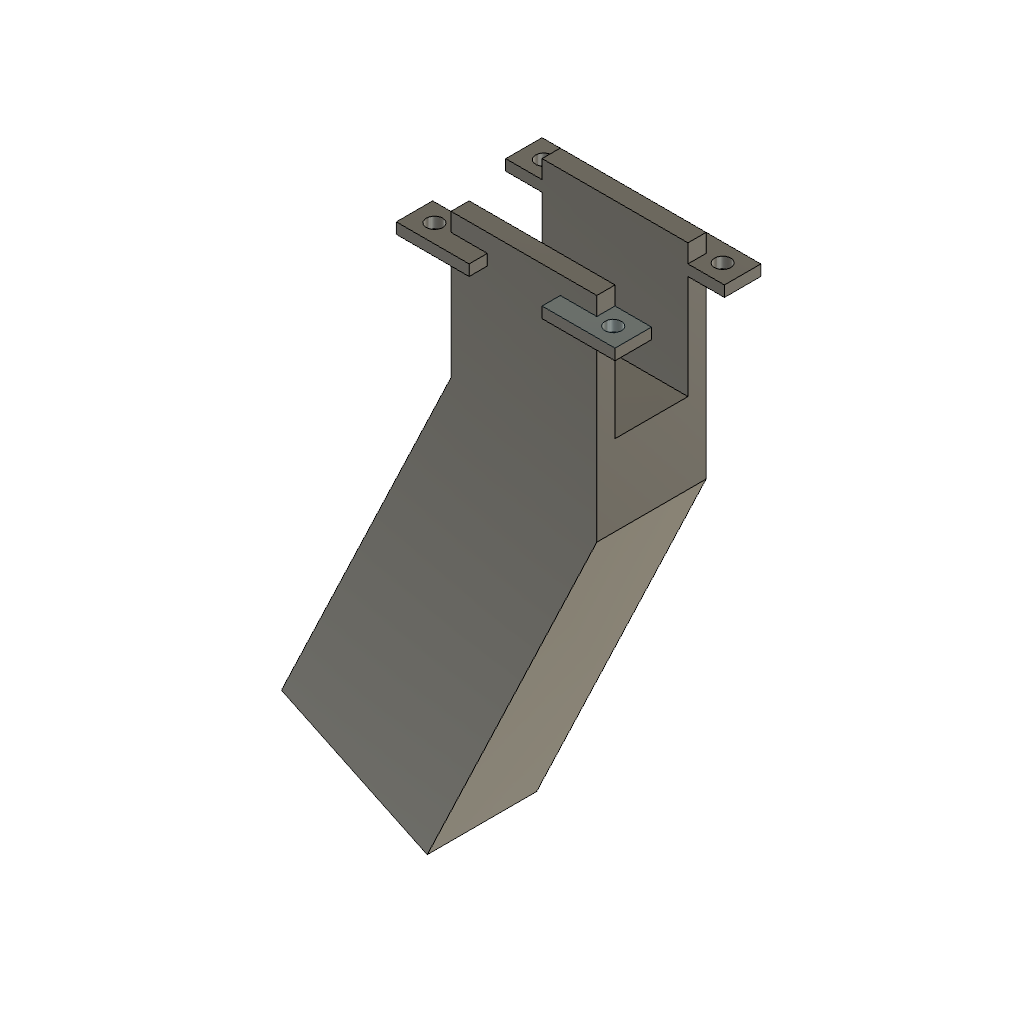
Servo Cover (Autodesk Fusion 360 design; units mm, degrees)
Autodesk Fusion 360 part; units mm, degrees
sketch "Sketch1" plane through (0, 0, 0) normal (0, 0, 1) x (1, 0, 0)
  line L0 (25, 15) -> (-25, 15)
  line L1 (-25, 15) -> (-25, -15)
  line L2 (-25, -15) -> (25, -15)
  line L3 (25, -15) -> (25, 15)
  line L4 (25, 15) -> (-25, -15) construction
  line L5 (-25, 15) -> (25, -15) construction
  line L6 (20, 10) -> (-20, 10)
  line L7 (-20, 10) -> (-20, -10)
  line L8 (-20, -10) -> (20, -10)
  line L9 (20, -10) -> (20, 10)
  line L10 (20, 10) -> (-20, -10) construction
  line L11 (-20, 10) -> (20, -10) construction
  line L12 (-20, -10) -> (-25, -10)
  line L13 (-20, 10) -> (-25, 10)
  line L14 (20, -10) -> (25, -10)
  line L15 (20, 10) -> (25, 10)
  line L16 (20, 7) -> (25, 7)
  line L17 (20, -7) -> (25, -7)
  line L18 (20, 10) -> (20, 15)
  line L19 (20, -10) -> (20, -15)
  line L20 (-20, 10) -> (-20, 15)
  line L21 (-20, -10) -> (-20, -15)
  dimension "d1" = 50
  dimension "d2" = 30
  dimension "d3" = 40
  dimension "d4" = 20
  dimension "d5" = 3
  dimension "d6" = 3
  constraint horizontal L0
  constraint perpendicular L0 L1
  constraint parallel L0 L2
  constraint parallel L1 L3
  constraint coincident L4 origin
  constraint coincident L5 origin
  constraint horizontal L6
  constraint perpendicular L6 L7
  constraint parallel L6 L8
  constraint parallel L7 L9
  constraint coincident L10 origin
  constraint coincident L11 origin
  constraint coincident L1 L12.end
  constraint perpendicular L1 L12
  constraint coincident L1 L13.end
  constraint perpendicular L1 L13
  constraint coincident L3 L14.end
  constraint perpendicular L3 L14
  constraint coincident L3 L15.end
  constraint perpendicular L3 L15
  constraint coincident L9 L16.start
  constraint coincident L3 L16.end
  constraint perpendicular L3 L16
  constraint coincident L9 L17.start
  constraint coincident L3 L17.end
  constraint perpendicular L3 L17
  constraint coincident L0 L18.end
  constraint perpendicular L0 L18
  constraint coincident L2 L19.end
  constraint perpendicular L2 L19
  constraint coincident L0 L20.end
  constraint perpendicular L0 L20
  constraint coincident L2 L21.end
  constraint perpendicular L2 L21
  measures "d1" distance of L1.end L2.end
  measures "d2" distance of L0.end L1.end
  measures "d3" distance of L7.end L8.end
  measures "d4" distance of L6.end L7.end
  measures "d5" distance of L14 L17
  measures "d6" distance of L15 L16
extrude "Extrude1" add sketch "Sketch1" along normal blind 36.5 contours L0 L6 L18 L20 | L2 L8 L19 L21 makes body 1 at (6.6667, 10, 12.1667) makes body 2 at (-6.6667, -10, 12.1667)
extrude "Extrude4" add sketch "Sketch1" against normal blind 3 contours L0 L6 L18 L20 | L6 L7 L8 L9 | L2 L8 L19 L21 bodies 1 2
sketch "Sketch17" plane through (20, 0, 0) normal (1, 0, 0) x (0, 1, 0)
  line L0 (15, -3) -> (15, 36.5)
  line L1 (15, 36.5) -> (10, 36.5)
  line L2 (10, 36.5) -> (10, 0)
  line L3 (10, 0) -> (-10, 0)
  line L4 (-10, 0) -> (-10, 36.5)
  line L5 (-10, 36.5) -> (-15, 36.5)
  line L6 (-15, 36.5) -> (-15, -3)
  line L7 (-15, -3) -> (15, -3)
  line L8 (-15, 31.5) -> (15, 31.5)
  line L9 (15, 31.5) -> (15, 28.5)
  line L10 (15, 28.5) -> (-15, 28.5)
  line L11 (-15, 28.5) -> (-15, 31.5)
  line L12 (-10, 31.5) -> (-10, 28.5)
  line L13 (10, 31.5) -> (10, 28.5)
  dimension "d34" = 3
  dimension "d35" = 31.5
  constraint horizontal L8
  constraint vertical L9
  constraint horizontal L10
  constraint vertical L11
  constraint coincident L6 L8.start
  constraint coincident L4 L12.start
  constraint coincident L8 L12.start
  constraint coincident L10 L12.end
  constraint coincident L4 L12.end
  constraint coincident L2 L13.start
  constraint coincident L8 L13.start
  constraint coincident L10 L13.end
  constraint coincident L2 L13.end
  measures "d34" distance of L8.start L10.end
  measures "d35" distance of L3 L8
extrude "Extrude9" add sketch "Sketch17" along normal blind 10 contours L0 L2 L8 L9 L10 L13 | L4 L6 L8 L10 L11 L12 bodies 1
sketch "Sketch18" plane through (0, -15, 0) normal (0, -1, 0) x (1, 0, 0)
  line L0 (20, -3) -> (20, 28.5)
  line L1 (20, 28.5) -> (30, 28.5)
  line L2 (30, 28.5) -> (30, 31.5)
  line L3 (30, 31.5) -> (20, 31.5)
  line L4 (20, 31.5) -> (20, 36.5)
  line L5 (20, 36.5) -> (-20, 36.5)
  line L6 (-20, -3) -> (20, -3)
  line L7 (30, 31.5) -> (10, 31.5)
  line L8 (20, 28.5) -> (10, 28.5)
  line L9 (10, 28.5) -> (10, 31.5)
  line L10 (10, 31.5) -> (30, 31.5)
  line L11 (30, 31.5) -> (30, 28.5)
  line L12 (30, 28.5) -> (10, 28.5)
  line L13 (10, 28.5) -> (10, 31.5)
  line L14 (-20, 36.5) -> (-20, -3)
  dimension "d49" = 20
  constraint horizontal L7
  constraint coincident L2.end L3.start
  constraint coincident L0.end L1.start
  constraint perpendicular L7 L9
  constraint horizontal L10
  constraint vertical L11
  constraint horizontal L12
  constraint vertical L13
  constraint coincident L1.end L2.start
  measures "d49" distance of L2.end L7.end
sketch "Sketch19" plane through (0, 15, 0) normal (0, 1, 0) x (-1, 0, 0)
  line L0 (20, 36.5) -> (-20, 36.5)
  line L1 (-20, 36.5) -> (-20, 31.5)
  line L2 (-20, 31.5) -> (-30, 31.5)
  line L3 (-30, 31.5) -> (-30, 28.5)
  line L4 (-30, 28.5) -> (-20, 28.5)
  line L5 (-20, 28.5) -> (-20, -3)
  line L6 (-20, -3) -> (20, -3)
  line L7 (-30, 31.5) -> (-10, 31.5)
  line L8 (-10, 31.5) -> (-10, 28.5)
  line L9 (-10, 28.5) -> (-30, 28.5)
  line L10 (-30, 28.5) -> (-30, 31.5)
  line L11 (20, -3) -> (20, 36.5)
  dimension "d50" = 20
  dimension "d51" = 3
  constraint horizontal L7
  constraint vertical L8
  constraint horizontal L9
  constraint vertical L10
  constraint coincident L2.end L3.start
  measures "d50" distance of L2.end L7.end
  measures "d51" distance of L2.end L3.end
extrude "Extrude10" add sketch "Sketch19" along normal blind 5 contours L2 L3 L4 L7 L8 L9 L10 bodies 1
extrude "Extrude11" add sketch "Sketch18" along normal blind 5 contours L1 L2 L3 L7 L8 L9 L10 L11 L12 L13 bodies 1
sketch "Sketch20" plane through (0, 0, 31.5) normal (0, 0, 1) x (-1, 0, 0)
  line L0 (-20, 10) -> (-20, 15)
  line L1 (-10, 20) -> (-30, 20)
  line L2 (-30, 20) -> (-30, 10)
  line L3 (-30, 10) -> (-20, 10)
  line L4 (-10, -20) -> (-30, -20)
  line L5 (-30, -20) -> (-30, -10)
  circle A0 centre (-24.5, -15) radius 2.25
  line L6 (-20, -10) -> (-20, -15)
  circle A1 centre (-24.5, 15) radius 2.25
  line L7 (-20, 15) -> (-10, 15)
  line L8 (-10, 15) -> (-10, 20)
  point P0 (-20, -10)
  point P1 (-30, -20)
  point P2 (-30, -10)
  dimension "d43" = 4.5
  dimension "d44" = 4.5
  dimension "d45" = 4.5
  dimension "d46" = 4.5
  constraint coincident P1 L4.end
  constraint coincident P2 L5.end
  measures "d43" diameter of A0
  measures "d44" distance of A0.centre L6
  measures "d45" diameter of A1
  measures "d46" distance of L0 A1.centre
extrude "Extrude12" cut sketch "Sketch20" against normal blind 3 contours A0 | A1 bodies 1
sketch "Sketch24" plane through (-20, 0, 0) normal (-1, 0, 0) x (0, -1, 0)
  line L0 (-10, 0) -> (-10, 36.5)
  line L1 (-10, 36.5) -> (-15, 36.5)
  line L2 (-15, 36.5) -> (-15, -3)
  line L3 (-15, -3) -> (15, -3)
  line L4 (15, -3) -> (15, 36.5)
  line L5 (15, 36.5) -> (10, 36.5)
  line L6 (10, 36.5) -> (10, 0)
  line L7 (10, 0) -> (-10, 0)
  line L8 (-20, 31.5) -> (20, 31.5)
  line L9 (20, 31.5) -> (20, 28.5)
  line L10 (20, 28.5) -> (-20, 28.5)
  line L11 (-20, 28.5) -> (-20, 31.5)
  line L12 (-10, 31.5) -> (-10, 28.5)
  line L13 (10, 31.5) -> (10, 28.5)
  line L14 (15, 31.5) -> (15, 28.5)
  line L15 (-15, 31.5) -> (-15, 28.5)
  point P0 (-20, 31.5)
  point P1 (20, 28.5)
  constraint horizontal L8
  constraint vertical L9
  constraint horizontal L10
  constraint vertical L11
  constraint coincident P1 L9.end
  constraint coincident P0 L8.start
  constraint coincident L8 L12.start
  constraint coincident L0 L12.start
  constraint coincident L10 L12.end
  constraint coincident L0 L12.end
  constraint coincident L6 L13.start
  constraint coincident L8 L13.start
  constraint coincident L10 L13.end
  constraint coincident L6 L13.end
  constraint coincident L4 L14.start
  constraint coincident L8 L14.start
  constraint coincident L4 L14.end
  constraint coincident L10 L14.end
  constraint coincident L8 L15.start
  constraint coincident L2 L15.start
  constraint coincident L10 L15.end
  constraint coincident L2 L15.end
extrude "Extrude13" add sketch "Sketch24" along normal blind 10 contours L0 L2 L8 L10 L12 L15 | L4 L6 L8 L10 L13 L14 bodies 1
sketch "Sketch25" plane through (0, 15, 0) normal (0, 1, 0) x (-1, 0, 0)
  line L0 (-10, 28.5) -> (-20, 28.5)
  line L1 (-20, 28.5) -> (-20, -3)
  line L2 (-20, -3) -> (20, -3)
  line L3 (20, -3) -> (20, 28.5)
  line L4 (20, 28.5) -> (30, 28.5)
  line L5 (30, 28.5) -> (30, 31.5)
  line L6 (30, 31.5) -> (20, 31.5)
  line L7 (20, 31.5) -> (20, 36.5)
  line L8 (20, 36.5) -> (-20, 36.5)
  line L9 (-20, 36.5) -> (-20, 31.5)
  line L10 (-20, 31.5) -> (-10, 31.5)
  line L11 (-10, 31.5) -> (-10, 28.5)
  line L12 (30, 31.5) -> (10, 31.5)
  line L13 (10, 31.5) -> (10, 28.5)
  line L14 (10, 28.5) -> (30, 28.5)
  line L15 (30, 28.5) -> (30, 31.5)
  dimension "d54" = 20
  constraint horizontal L12
  constraint vertical L13
  constraint horizontal L14
  constraint vertical L15
  constraint coincident L5.end L6.start
  measures "d54" distance of L5.end L12.end
extrude "Extrude14" add sketch "Sketch25" along normal blind 5 contours L4 L5 L6 L12 L13 L14 L15 bodies 1
sketch "Sketch26" plane through (0, -15, 0) normal (0, -1, 0) x (1, 0, 0)
  line L0 (10, 31.5) -> (20, 31.5)
  line L1 (20, 31.5) -> (20, 36.5)
  line L2 (20, 36.5) -> (-20, 36.5)
  line L3 (-20, 36.5) -> (-20, 31.5)
  line L4 (-20, 31.5) -> (-30, 31.5)
  line L5 (-30, 31.5) -> (-30, 28.5)
  line L6 (-30, 28.5) -> (-20, 28.5)
  line L7 (-20, 28.5) -> (-20, -3)
  line L8 (-20, -3) -> (20, -3)
  line L9 (20, -3) -> (20, 28.5)
  line L10 (20, 28.5) -> (10, 28.5)
  line L11 (10, 28.5) -> (10, 31.5)
  line L12 (-30, 31.5) -> (-10, 31.5)
  line L13 (-10, 31.5) -> (-10, 28.5)
  line L14 (-10, 28.5) -> (-30, 28.5)
  line L15 (-30, 28.5) -> (-30, 31.5)
  dimension "d57" = 20
  constraint horizontal L12
  constraint vertical L13
  constraint horizontal L14
  constraint vertical L15
  constraint coincident L4.end L5.start
  measures "d57" distance of L4.end L12.end
extrude "Extrude15" add sketch "Sketch26" along normal blind 5 contours L4 L5 L6 L12 L13 L14 L15 bodies 1
sketch "Sketch27" plane through (0, 0, 31.5) normal (0, 0, 1) x (-1, 0, 0)
  line L0 (20, 15) -> (20, 10)
  line L1 (20, 10) -> (30, 10)
  line L2 (30, 10) -> (30, 20)
  line L3 (30, 20) -> (10, 20)
  line L4 (10, 20) -> (10, 15)
  line L5 (10, 15) -> (20, 15)
  line L6 (30, -20) -> (10, -20)
  circle A0 centre (24.5, -15) radius 2.25
  line L7 (20, -15) -> (20, -10)
  circle A1 centre (24.5, 15) radius 2.25
  point P0 (20, -10)
  point P1 (30, -20)
  point P2 (30, -10)
  dimension "d60" = 4.5
  dimension "d61" = 4.5
  dimension "d62" = 4.5
  dimension "d63" = 4.5
  measures "d60" diameter of A0
  measures "d61" distance of A0.centre L7
  measures "d62" diameter of A1
  measures "d63" distance of L0 A1.centre
extrude "Extrude16" cut sketch "Sketch27" against normal blind 3 contours A0 | A1 bodies 1
sketch "Sketch30" plane through (0, 0, 31.5) normal (0, 0, 1) x (-1, 0, 0)
  circle A0 centre (-24.5, 15) radius 2.25
  line L0 (-20, 10) -> (-20, 15)
  line L1 (-20, 15) -> (-10, 15)
  line L2 (-10, 15) -> (-10, 20)
  line L3 (-10, 20) -> (-30, 20)
  line L4 (-30, 20) -> (-30, 10)
  line L5 (-30, 10) -> (-20, 10)
sketch "Sketch31" plane through (0, -15, 0) normal (0, -1, 0) x (1, 0, 0)
  line L0 (-10, 28.5) -> (-20, 28.5)
  line L1 (-20, 28.5) -> (-20, -3)
  line L2 (-20, -3) -> (20, -3)
  line L3 (20, -3) -> (20, 28.5)
  line L4 (20, 28.5) -> (10, 28.5)
  line L5 (10, 28.5) -> (10, 31.5)
  line L6 (10, 31.5) -> (20, 31.5)
  line L7 (20, 31.5) -> (20, 36.5)
  line L8 (20, 36.5) -> (-20, 36.5)
  line L9 (-20, 36.5) -> (-20, 31.5)
  line L10 (-20, 31.5) -> (-10, 31.5)
  line L11 (-10, 31.5) -> (-10, 28.5)
  line L12 (20, -3) -> (20, -14)
  line L13 (-20, -3) -> (20.4535, -22.2953)
  line L14 (-20, -3) -> (24.8196, -3) construction
  line L15 (20, -14) -> (20, -25.4187)
  dimension "d66" = 25.5
  constraint coincident L2.end L3.start
  constraint perpendicular L2 L12
  constraint horizontal L14
  constraint coincident L1.end L2.start
  constraint parallel L12 L15
  measures "d66" angle of L13 L14
extrude "Extrude17" add sketch "Sketch31" against normal blind 30 contours L2 L12 L13 L15 bodies 1
extrude "Extrude18" add 1 faces at (-6.6667, -5, -9.3597) along direction (-0.430511, 0, -0.902585) blind 108 on bodies 1 bodies 1
sketch "Sketch32" plane through (-51.3677, 0, -107.6947) normal (-0.430511, 0, -0.902585) x (0, -1, 0)
  line L0 (15, -27.557) -> (15, 16.7602)
  line L1 (15, 16.7602) -> (-15, 16.7602)
  line L2 (-15, 16.7602) -> (-15, -27.557)
  line L3 (-15, -27.557) -> (15, -27.557)
  circle A0 centre (7.38, -19.937) radius 1.875
  circle A1 centre (-7.38, 9.1402) radius 1.875
  dimension "d71" = 3.75
  dimension "d72" = 3.75
  dimension "d73" = 7.62
  dimension "d74" = 7.62
  dimension "d75" = 7.62
  dimension "d76" = 7.62
  measures "d71" diameter of A0
  measures "d72" diameter of A1
  measures "d73" distance of L0 A0.centre
  measures "d74" distance of L3 A0.centre
  measures "d75" distance of L2 A1.centre
  measures "d76" distance of L1 A1.centre
extrude "Extrude19" cut sketch "Sketch32" against normal blind 8 contours A0 | A1 bodies 1
